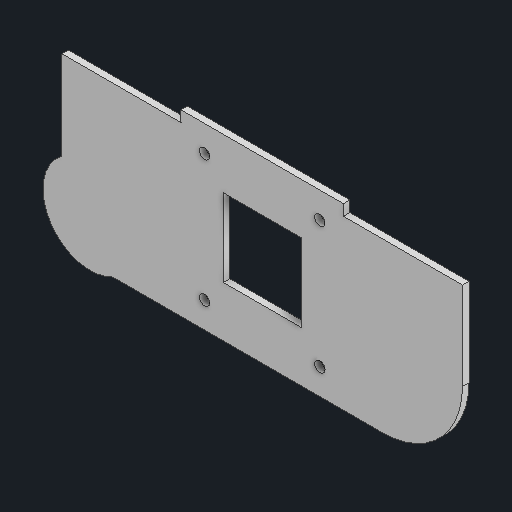
# Autodesk Inventor part: support_peltier_boite
Saved by Autodesk Inventor 2026.1 (Build 301233020, 233B)
## iProperties
Created: 2026-06-08
Part Number: support_peltier_boite
Material: Générique
Document SubType Name: Modeling
Designer: matpo
Density: 1 g/cm^3
Appearance: Par défaut
Author: matpo
Autodesk Inventor part; units mm, degrees
ref_plane "YZ Plane" through (0, 0, 0) normal (1, 0, 0) x (0, 1, 0)
ref_plane "XZ Plane" through (0, 0, 0) normal (0, 1, 0) x (-1, 0, 0)
ref_plane "XY Plane" through (0, 0, 0) normal (0, 0, 1) x (1, 0, 0)
sketch "Esquisse1" plane through (0, 0, 0) normal (0, 0, 1) x (1, 0, 0)
  line L0 (-37, 86) -> (37, 86)
  arc A0 (-37, 86) -> (-62, 61) centre (-37, 61) ccw
  line L1 (-62, -61) -> (-62, 61)
  arc A1 (-62, -61) -> (-39.0765, -67.1104) centre (-52.8758, -72.8248) ccw
  line L2 (34.9068, -86) -> (-39.0765, -86)
  arc A2 (34.9068, -68.6836) -> (62, -61) centre (37, -61) ccw
  line L3 (62, 61) -> (62, -61)
  arc A3 (62, 61) -> (37, 86) centre (37, 61) ccw
  arc A4 (-61.6, -61.1983) -> (-45.9417, -85.6) centre (-52.8758, -72.8248) ccw
  line L4 (-61.6, -61.1983) -> (-61.6, 61)
  arc A5 (-37, 85.6) -> (-61.6, 61) centre (-37, 61) ccw
  line L5 (-37, 85.6) -> (37, 85.6)
  arc A6 (61.6, 61) -> (37, 85.6) centre (37, 61) ccw
  line L6 (61.6, 61) -> (61.6, -61)
  arc A7 (37, -85.6) -> (61.6, -61) centre (37, -61) ccw
  line L7 (37, -85.6) -> (-45.9417, -85.6)
  line L8 (-25, -85.6) -> (25, -85.6)
  line L9 (25, -85.6) -> (25, -30.6)
  line L10 (25, -30.6) -> (-25, -30.6)
  line L11 (-25, -30.6) -> (-25, -85.6)
  line L12 (-25, -85.6) -> (25, -30.6) construction
  line L13 (25, -85.6) -> (-25, -30.6) construction
  line L14 (-25, -85.6) -> (-25, -53.8421)
  line L15 (-45.9417, -85.6) -> (-25, -85.6)
  line L16 (-61.6, -33.9568) -> (-61.6, -61.1983)
  line L17 (-61.6, -33.9568) -> (61.6, -33.9568)
  line L18 (34.9068, -68.6836) -> (-39.0765, -67.1104)
  line L19 (11.95, -70.05) -> (-11.95, -70.05)
  line L20 (-11.95, -70.05) -> (-11.95, -46.15)
  line L21 (-11.95, -46.15) -> (11.95, -46.15)
  line L22 (11.95, -46.15) -> (11.95, -70.05)
  line L23 (11.95, -70.05) -> (-11.95, -46.15) construction
  line L24 (-11.95, -70.05) -> (11.95, -46.15) construction
  circle A8 centre (17.7273, -38.6) radius 1.6
  circle A9 centre (-17.7273, -38.6) radius 1.6
  circle A10 centre (17.7273, -77.6) radius 1.6
  circle A11 centre (-17.7273, -77.6) radius 1.6
  line L25 (-31.9997, -40.0553) -> (-32.3398, -56.0516)
  arc A12 (-31.9997, -40.0553) -> (-33.3186, -37.9924) centre (-34.1992, -40.0085) ccw
  spline S0 degree 3 poles (-34.9932, -37.9568) (-34.7219, -37.8518) (-34.4281, -37.8031) (-33.8766, -37.8148) (-33.5852, -37.8759) (-33.3186, -37.9924) knots 0.595499 0.595499 0.595499 0.595499 0.678242 0.678242 0.760985 0.760985 0.760985 0.760985
  arc A13 (-34.9932, -37.9568) -> (-36.3987, -39.9617) centre (-34.1992, -40.0085) ccw
  line L26 (-36.7388, -55.9581) -> (-36.3987, -39.9617)
  arc A14 (-36.7388, -55.9581) -> (-32.3398, -56.0516) centre (-34.5393, -56.0049) ccw
  point P0 (0, 0)
  point P1 (-32.7, -77.0005)
  point P2 (0, -58.1)
  point P3 (-4.4709, -85.6)
  point P4 (25, -33.9568)
  point P5 (-25, -33.9568)
  point P6 (-30.8721, -57.5763)
extrude "Extrusion1" add sketch "Esquisse1" along normal blind 2 contours L7 A4 L4 L17 L11 L18 A1 | A1 L18 L11 L7 | A7 L7 L9 L18 A2 | A2 L18 L9 L17 L6 A7 | L11 L18 L20 L19 L22 L9 L7 | L11 L17 L9 L18 L22 L21 L20 | L17 L11 L10 L9 | L25 A14 L26 A13 S0 A12
